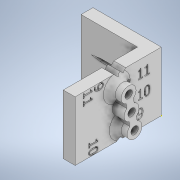
# Autodesk Inventor part: v3_gaura_9mm_semn
Saved by Autodesk Inventor 2022.6 (Build 266554000, 554)
## iProperties
Created: 2026-01-08
Part Number: v3_gaura_9mm_semn
Material: Generic
Document SubType Name: Modeling
Designer: Dragos Macovei
Density: 1 g/cm^3
Appearance: Default
Author: Dragos Macovei
Autodesk Inventor part; units mm, degrees
ref_plane "YZ Plane" through (0, 0, 0) normal (1, 0, 0) x (0, 1, 0)
ref_plane "XZ Plane" through (0, 0, 0) normal (0, 1, 0) x (-1, 0, 0)
ref_plane "XY Plane" through (0, 0, 0) normal (0, 0, 1) x (1, 0, 0)
sketch "Sketch1" plane through (0, 0, 0) normal (0, 1, 0) x (-1, 0, 0)
  line L0 (0, 0) -> (23, 0)
  line L1 (23, 4) -> (4, 4)
  line L2 (4, 4) -> (4, 29)
  line L3 (4, 29) -> (0, 29)
  line L4 (0, 29) -> (0, 0)
  line L5 (23, 4) -> (23, 0)
  point P0 (4, 16.5)
  point P1 (27, 14.5)
  point P2 (25, 29)
  dimension "d1" = 4
  dimension "d3" = 4
  dimension "d4" = 25
  dimension "d5" = 25
  constraints: 12 end point, 4 perpendicular, 1 horizontal, 1 midpoint
  measures "d1" distance from line of L4 point (4, 16.5)
  measures "d3" distance between parallel lines of L0 L1
  measures "d4" distance from line of L1 point (25, 29)
  measures "d5" distance from line of L1 L3.end
extrude "Extrusion1" add sketch "Sketch1" along normal blind 20
sketch "Sketch2" plane through (0, 0, 29) normal (1, 0, 0) x (0, 0, -1)
  point P0 (29, 0)
sketch "Sketch7" plane through (0, 0, 0) normal (0, 0, -1) x (-1, 0, 0)
  line L0 (0, 0) -> (23, 0) projected
  line L1 (0, 20) -> (23, 20) projected
  line L2 (0, 0) -> (0, 20) projected
  line L3 (13.5, 10) -> (10.5, 10)
  line L4 (10.5, 10) -> (10.5, 9.5)
  line L5 (10.5, 9.5) -> (13.5, 9.5)
  line L6 (13.5, 9.5) -> (13.5, 10)
  line L7 (13.5, 10) -> (16.5, 10)
  line L8 (16.5, 10) -> (16.5, 9.5)
  line L9 (16.5, 9.5) -> (13.5, 9.5)
  line L10 (13.5, 9.5) -> (13.5, 10)
  line L11 (16.5, 10) -> (10.5, 10)
  line L12 (10.5, 10) -> (10.5, 10.5)
  line L13 (10.5, 10.5) -> (16.5, 10.5)
  line L14 (16.5, 10.5) -> (16.5, 10)
  line L15 (23, 0) -> (23, 20) projected
  dimension "d25" = 3
  dimension "d26" = 0.5
  dimension "d27" = 3
  dimension "d28" = 0.5
  dimension "d29" = 0.5
  constraints: 24 end point, 6 parallel, 3 horizontal, 3 perpendicular, 1 point on line
  measures "d25" distance of L5.end L4.end
  measures "d26" distance of L4.end L3.end
  measures "d27" distance of L8.end L9.end
  measures "d28" distance of L7.end L8.end
  measures "d29" distance of L11.end L12.end
extrude "Extrusion6" cut sketch "Sketch7" against normal through all contours L6 L5 L4 L3 | L7 L8 L9 L6 | L3 L12 L13 L14 L7
fillet "Fillet3" radius 3 4 edges at (-13.5, 10.5, 0) (-16.5, 10, 0) (-13.5, 9.5, 0) (-10.5, 10, 0) inverted yes
sketch "Sketch8" plane through (0, 0, 0) normal (0, 0, -1) x (-1, 0, 0)
  line L0 (16.5, 9.5) -> (16.5, 10.5) projected
  line L1 (10.5, 10.5) -> (10.5, 9.5) projected
  line L2 (7.5, 13.5) -> (7.5, 6.5) projected
  line L3 (19.5, 6.5) -> (19.5, 13.5) projected
  line L4 (16.5, 10.5) -> (19.5, 10)
  line L5 (16.5, 9.5) -> (19.5, 10)
  line L6 (16.5, 10.5) -> (10.5, 10.5) projected
  line L7 (10.5, 10.5) -> (7.5, 10)
  line L8 (7.5, 10) -> (10.5, 9.5)
  point P0 (0, 0)
  point P1 (16.5, 10)
  point P2 (10.5, 10)
  constraints: 8 end point, 4 midpoint, 2 parallel
extrude "Extrusion7" cut sketch "Sketch8" along normal through all both and the other way through all
sketch "Sketch9" plane through (-4, 0, 4) normal (-1, 0, 0) x (0, 0, 1)
  circle A0 centre (9, 4.25) radius 1.25
  circle A1 centre (10, 10) radius 1.25
  circle A2 centre (11, 15.75) radius 1.25
  line L0 (0, 0) -> (25, 0) projected
  line L1 (0, 0) -> (0, 20) projected
  line L2 (0, 20) -> (25, 20) projected
  point P0 (-4, 0)
  point P1 (10, 20)
  dimension "d35" = 2.5
  dimension "d36" = 2.5
  dimension "d37" = 2.5
  dimension "d40" = 3
  dimension "d41" = 9
  dimension "d42" = 10
  dimension "d43" = 11
  dimension "d48" = 3
  dimension "d49" = 5.75
  constraints: 3 centre point
  measures "d35" diameter of A0
  measures "d36" diameter of A1
  measures "d37" diameter of A2
  measures "d40" distance edge to line of A0 L0
  measures "d41" distance from line of L1 A0.centre
  measures "d42" distance from line of L1 A1.centre
  measures "d43" distance from line of L1 A2.centre
  measures "d48" distance edge to line of A2 L2
  measures "d49" vertical distance of A1.centre A0.centre
extrude "Extrusion8" cut sketch "Sketch9" against normal through all
sketch "Sketch10" plane through (-4, 0, 4) normal (-1, 0, 0) x (0, 0, 1)
  circle A0 centre (11, 15.75) radius 1.25 projected
  circle A1 centre (10, 10) radius 1.25 projected
  circle A2 centre (9, 4.25) radius 1.25 projected
  line L0 (0, 0) -> (25, 0) projected
  line L1 (25, 0) -> (25, 20) projected
  line L2 (0, 20) -> (25, 20) projected
  line L3 (0, 0) -> (0, 20) projected
  line L4 (0, 0) -> (25, 0) projected
  line L5 (25, 20) -> (-4, 20) projected
  circle A3 centre (10, 0) radius 1
  line L6 (9, 0) -> (10, 1)
  line L7 (11, 0) -> (10, 1)
  circle A4 centre (11, 20) radius 1
  circle A5 centre (9, 20) radius 1
  line L8 (8, 20) -> (9, 19)
  line L9 (10, 20) -> (9, 19)
  line L10 (10, 20) -> (11, 19)
  line L11 (12, 20) -> (11, 19)
  point P0 (-4, 0)
  point P1 (11, 0)
  point P2 (11, 0)
  constraints: 12 end point, 9 point on circle, 8 point on line, 4 perpendicular, 3 centre point, 3 coincident
extrude "Extrusion9" cut sketch "Sketch10" against normal through all contours L6 L7 L0 | L2 L9 L8 | L2 L11 L10
sketch "Sketch11" plane through (0, 0, 29) normal (1, 0, 0) x (0, 0, -1)
  line L0 (14, 19) -> (13, 20) projected
  line L1 (0, 20) -> (13, 20) projected
  line L2 (0, 0) -> (0, 20) projected
  line L3 (0, 0) -> (14, 0) projected
  line L4 (14, 0) -> (15, 1) projected
  line L5 (15, 1) -> (16, 0) projected
  line L6 (16, 0) -> (29, 0) projected
  line L7 (29, 0) -> (29, 20) projected
  line L8 (17, 20) -> (29, 20) projected
  line L9 (17, 20) -> (16, 19) projected
  line L10 (16, 19) -> (15, 20) projected
  line L11 (15, 20) -> (14, 19) projected
  circle A0 centre (14, 15.75) radius 1.25 projected
  circle A1 centre (15, 10) radius 1.25 projected
  circle A2 centre (16, 4.25) radius 1.25 projected
  circle A3 centre (14, 15.75) radius 2.5
  circle A4 centre (15, 10) radius 2.5
  circle A5 centre (16, 4.25) radius 2.5
  dimension "d52" = 5
  dimension "d53" = 5
  dimension "d54" = 5
  constraints: 3 centre point, 3 coincident
  measures "d52" diameter of A3
  measures "d53" diameter of A4
  measures "d54" diameter of A5
extrude "Extrusion10" add sketch "Sketch11" along normal blind 4 contours A3 | A4 | A5
fillet "Fillet4" radius 2 1 edges at (0, 15.75, 17.5)
fillet "Fillet5" radius 2 1 edges at (0, 4.25, 15.5)
sketch "Sketch12" plane through (4, 10, 14) normal (1, 0, 0) x (0, 0, -1)
  circle A0 centre (-1, 5.75) radius 1.25 projected
  line L0 (-2.25, 5.75) -> (-0.2318, -5.9623)
  circle A1 centre (1, -5.75) radius 1.25 projected
  line L1 (-0.0128, 7.3687) -> (2.5592, -7.42)
  circle A2 centre (0, 0) radius 2.5 projected
  circle A3 centre (0, 0) radius 1.25 projected
  circle A4 centre (-1, 5.75) radius 2.5 projected
  circle A5 centre (-1, 5.75) radius 1.25 projected
  circle A6 centre (1, -5.75) radius 2.5 projected
  circle A7 centre (1, -5.75) radius 1.25 projected
  point P0 (14, -10)
  point P1 (-0.5995, -3.8286)
  point P2 (1.8606, -3.4028)
  point P3 (1.6025, -1.9189)
  point P4 (-0.8544, -2.3495)
  point P5 (0.6025, 3.8311)
  point P6 (-1.8445, 3.397)
  point P7 (-1.5914, 1.928)
  point P8 (0.8606, 2.3472)
  constraints: 4 end point, 1 horizontal alignment, 6 other
extrude "Extrusion11" add sketch "Sketch12" against normal blind 4 contours L1 A2 L0 A4 | A2 L1 A6 L0
sketch "Sketch13" plane through (0, 0, 29) normal (1, 0, 0) x (0, 0, -1)
  line L0 (20.7455, 17.3) -> (27.0793, 17.3) construction
  line L1 (27.0793, 17.3) -> (27.0793, 14.5773) construction
  line L2 (27.0793, 14.5773) -> (20.7455, 14.5773) construction
  line L3 (20.7455, 14.5773) -> (20.7455, 17.3) construction
  arc A0 (17.479, 0) -> (17.0831, 8.6177) centre (16, 4.25) ccw projected
  line L4 (17.479, 0) -> (29, 0) projected
  line L5 (29, 0) -> (29, 20) projected
  line L6 (17, 20) -> (29, 20) projected
  line L7 (17, 20) -> (16.495, 19.495) projected
  arc A1 (16.4941, 12.0044) -> (16.495, 19.495) centre (14, 15.75) ccw projected
  arc A2 (17.0831, 8.6177) -> (16.4941, 12.0044) centre (15, 10) ccw projected
  line L8 (20.7455, 11.3312) -> (27.0847, 11.3312) construction
  line L9 (27.0847, 11.3312) -> (27.0847, 8.61) construction
  line L10 (27.0847, 8.61) -> (20.7455, 8.61) construction
  line L11 (20.7455, 8.61) -> (20.7455, 11.3312) construction
  line L12 (20.7455, 5.8) -> (27.0538, 5.8) construction
  line L13 (27.0538, 5.8) -> (27.0538, 3.0514) construction
  line L14 (27.0538, 3.0514) -> (20.7455, 3.0514) construction
  line L15 (20.7455, 3.0514) -> (20.7455, 5.8) construction
  line L16 (20.7455, 15.75) -> (20.7455, 4.25)
  line L17 (22.6944, 14.2421) -> (21.2074, 14.2421)
  line L18 (21.2074, 14.2421) -> (21.2074, 14.5533)
  line L19 (21.2074, 14.5533) -> (21.7607, 14.5533)
  line L20 (21.7607, 14.5533) -> (21.7607, 16.596)
  line L21 (21.7607, 16.596) -> (21.2074, 16.596)
  line L22 (21.2074, 16.596) -> (21.2074, 16.8752)
  spline S0 degree 2 poles (21.2074, 16.8752) (21.5211, 16.8752) (21.8175, 17.053) (21.8373, 17.3) knots 0 0 0 1 2 2 2
  line L23 (21.8373, 17.3) -> (22.1534, 17.3)
  line L24 (22.1534, 17.3) -> (22.1534, 14.5533)
  line L25 (22.1534, 14.5533) -> (22.6944, 14.5533)
  line L26 (22.6944, 14.5533) -> (22.6944, 14.2421)
  line L27 (24.9816, 14.2421) -> (23.4947, 14.2421)
  line L28 (23.4947, 14.2421) -> (23.4947, 14.5533)
  line L29 (23.4947, 14.5533) -> (24.0479, 14.5533)
  line L30 (24.0479, 14.5533) -> (24.0479, 16.596)
  line L31 (24.0479, 16.596) -> (23.4947, 16.596)
  line L32 (23.4947, 16.596) -> (23.4947, 16.8752)
  spline S1 degree 2 poles (23.4947, 16.8752) (23.8084, 16.8752) (24.1048, 17.053) (24.1245, 17.3) knots 0 0 0 1 2 2 2
  line L33 (24.1245, 17.3) -> (24.4407, 17.3)
  line L34 (24.4407, 17.3) -> (24.4407, 14.5533)
  line L35 (24.4407, 14.5533) -> (24.9816, 14.5533)
  line L36 (24.9816, 14.5533) -> (24.9816, 14.2421)
  line L37 (22.6944, 8.2215) -> (21.2074, 8.2215)
  line L38 (21.2074, 8.2215) -> (21.2074, 8.5327)
  line L39 (21.2074, 8.5327) -> (21.7607, 8.5327)
  line L40 (21.7607, 8.5327) -> (21.7607, 10.5754)
  line L41 (21.7607, 10.5754) -> (21.2074, 10.5754)
  line L42 (21.2074, 10.5754) -> (21.2074, 10.8545)
  spline S2 degree 2 poles (21.2074, 10.8545) (21.5211, 10.8545) (21.8175, 11.0324) (21.8373, 11.2794) knots 0 0 0 1 2 2 2
  line L43 (21.8373, 11.2794) -> (22.1534, 11.2794)
  line L44 (22.1534, 11.2794) -> (22.1534, 8.5327)
  line L45 (22.1534, 8.5327) -> (22.6944, 8.5327)
  line L46 (22.6944, 8.5327) -> (22.6944, 8.2215)
  spline S3 degree 2 poles (25.152, 9.7455) (25.152, 8.9254) (24.6753, 8.1573) (24.1789, 8.1573) knots 0 0 0 1 2 2 2
  spline S4 degree 2 poles (24.1789, 8.1573) (23.675, 8.1573) (23.2032, 8.9403) (23.2032, 9.743) knots 0 0 0 1 2 2 2
  spline S5 degree 2 poles (23.2032, 9.743) (23.2032, 10.568) (23.6799, 11.3312) (24.1789, 11.3312) knots 0 0 0 1 2 2 2
  spline S6 degree 2 poles (24.1789, 11.3312) (24.6803, 11.3312) (25.152, 10.5408) (25.152, 9.7455) knots 0 0 0 1 2 2 2
  spline S7 degree 2 poles (24.6284, 8.8168) (24.6877, 8.9674) (24.7371, 9.4318) (24.7371, 9.7455) knots 0 0 0 1 2 2 2
  spline S8 degree 2 poles (24.7371, 9.7455) (24.7371, 10.0592) (24.6877, 10.5211) (24.6259, 10.6767) knots 0 0 0 1 2 2 2
  spline S9 degree 2 poles (24.6259, 10.6767) (24.5642, 10.8323) (24.3493, 10.9928) (24.1789, 10.9928) knots 0 0 0 1 2 2 2
  spline S10 degree 2 poles (24.1789, 10.9928) (24.0084, 10.9928) (23.7886, 10.8323) (23.7244, 10.6717) knots 0 0 0 1 2 2 2
  spline S11 degree 2 poles (23.7244, 10.6717) (23.6626, 10.5161) (23.6182, 10.0419) (23.6182, 9.743) knots 0 0 0 1 2 2 2
  spline S12 degree 2 poles (23.6182, 9.743) (23.6182, 9.4219) (23.6577, 8.9921) (23.7219, 8.8242) knots 0 0 0 1 2 2 2
  spline S13 degree 2 poles (23.7219, 8.8242) (23.7812, 8.6661) (24.001, 8.4957) (24.1789, 8.4957) knots 0 0 0 1 2 2 2
  spline S14 degree 2 poles (24.1789, 8.4957) (24.3468, 8.4957) (24.5666, 8.6562) (24.6284, 8.8168) knots 0 0 0 1 2 2 2
  spline S15 degree 2 poles (20.8839, 4.7478) (20.8839, 4.9824) (21.037, 5.3727) (21.1704, 5.5135) knots 0 0 0 1 2 2 2
  spline S16 degree 2 poles (21.1704, 5.5135) (21.2963, 5.6493) (21.6644, 5.8) (21.8521, 5.8) knots 0 0 0 1 2 2 2
  spline S17 degree 2 poles (21.8521, 5.8) (22.0621, 5.8) (22.4029, 5.6592) (22.5289, 5.5258) knots 0 0 0 1 2 2 2
  spline S18 degree 2 poles (22.5289, 5.5258) (22.687, 5.3579) (22.8599, 4.8145) (22.8599, 4.397) knots 0 0 0 1 2 2 2
  spline S19 degree 2 poles (22.8599, 4.397) (22.8599, 4.0191) (22.6894, 3.3423) (22.5239, 3.1176) knots 0 0 0 1 2 2 2
  spline S20 degree 2 poles (22.5239, 3.1176) (22.3486, 2.8804) (21.8546, 2.631) (21.4939, 2.631) knots 0 0 0 1 2 2 2
  spline S21 degree 2 poles (21.4939, 2.631) (21.4124, 2.631) (21.2272, 2.6483) (21.1481, 2.673) knots 0 0 0 1 2 2 2
  line L47 (21.1481, 2.673) -> (21.1481, 3.0657)
  line L48 (21.1481, 3.0657) -> (21.1679, 3.0657)
  spline S22 degree 2 poles (21.1679, 3.0657) (21.2198, 3.0361) (21.4371, 2.9842) (21.5483, 2.9842) knots 0 0 0 1 2 2 2
  spline S23 degree 2 poles (21.5483, 2.9842) (21.9484, 2.9842) (22.4054, 3.5128) (22.4375, 4.0018) knots 0 0 0 1 2 2 2
  spline S24 degree 2 poles (22.4375, 4.0018) (22.2745, 3.8907) (21.9781, 3.7894) (21.8027, 3.7894) knots 0 0 0 1 2 2 2
  spline S25 degree 2 poles (21.8027, 3.7894) (21.6347, 3.7894) (21.3556, 3.8635) (21.2148, 3.9697) knots 0 0 0 1 2 2 2
  spline S26 degree 2 poles (21.2148, 3.9697) (21.0518, 4.0957) (20.8839, 4.4785) (20.8839, 4.7478) knots 0 0 0 1 2 2 2
  spline S27 degree 2 poles (22.4474, 4.4884) (22.4474, 4.7972) (22.3338, 5.1874) (22.2325, 5.2936) knots 0 0 0 1 2 2 2
  spline S28 degree 2 poles (22.2325, 5.2936) (22.1436, 5.3924) (21.9583, 5.4665) (21.8496, 5.4665) knots 0 0 0 1 2 2 2
  spline S29 degree 2 poles (21.8496, 5.4665) (21.5977, 5.4665) (21.2988, 5.1059) (21.2988, 4.7651) knots 0 0 0 1 2 2 2
  spline S30 degree 2 poles (21.2988, 4.7651) (21.2988, 4.5724) (21.3976, 4.3229) (21.5063, 4.234) knots 0 0 0 1 2 2 2
  spline S31 degree 2 poles (21.5063, 4.234) (21.5853, 4.1698) (21.7805, 4.1278) (21.8941, 4.1278) knots 0 0 0 1 2 2 2
  spline S32 degree 2 poles (21.8941, 4.1278) (22.025, 4.1278) (22.3263, 4.2192) (22.44, 4.2958) knots 0 0 0 1 2 2 2
  spline S33 degree 2 poles (22.44, 4.2958) (22.4424, 4.3254) (22.4474, 4.4267) (22.4474, 4.4884) knots 0 0 0 1 2 2 2
  point P0 (20.7455, 9.7812)
  dimension "d61" = 1.55
  dimension "d62" = 1.55
  dimension "d63" = 1.55
  dimension "d64" = 0
  constraints: 5 coincident, 3 point on line, 2 end point, 1 vertical, 6 other
  measures "d61" distance of point (20.746, 4.25) point (20.746, 5.8)
  measures "d62" distance of point (20.746, 9.781) point (20.746, 11.331)
  measures "d63" distance of L16.start point (20.746, 17.3)
  measures "d64" vertical distance of L16.start A1.centre
extrude "Extrusion12" cut sketch "Sketch13" against normal blind 1.5 contours L17 L18 L19 L20 L21 L22 S0 L23 L24 L25 L26 | L27 L28 L29 L30 L31 L32 S1 L33 L34 L35 L36 | L37 L38 L39 L40 L41 L42 S2 L43 L44 L45 L46 | S3 S4 S5 S6 | S15 S16 S17 S18 S19 S20 S21 L47 L48 S22 S23 S24 S25 S26
sketch "Sketch14" plane through (0, 0, 29) normal (1, 0, 0) x (0, 0, -1)
  line L0 (7.6929, 4.5921) -> (7.6929, 0.0177) construction
  line L1 (7.6929, 0.0177) -> (4.519, 0.0177) construction
  line L2 (4.519, 0.0177) -> (4.519, 4.5921) construction
  line L3 (4.519, 4.5921) -> (7.6929, 4.5921) construction
  line L4 (9.5182, 19.9679) -> (9.5182, 15.3934) construction
  line L5 (9.5182, 15.3934) -> (6.3442, 15.3934) construction
  line L6 (6.3442, 15.3934) -> (6.3442, 19.9679) construction
  line L7 (6.3442, 19.9679) -> (9.5182, 19.9679) construction
  line L8 (2.5663, 20.0123) -> (5.7403, 20.0123) construction
  line L9 (5.7403, 20.0123) -> (5.7403, 15.4378) construction
  line L10 (5.7403, 15.4378) -> (2.5663, 15.4378) construction
  line L11 (2.5663, 15.4378) -> (2.5663, 20.0123) construction
  spline S0 degree 2 poles (8.466, 19.8295) (8.7006, 19.8295) (9.0909, 19.6764) (9.2317, 19.543) knots 0 0 0 1 2 2 2
  spline S1 degree 2 poles (9.2317, 19.543) (9.3675, 19.417) (9.5182, 19.049) (9.5182, 18.8613) knots 0 0 0 1 2 2 2
  spline S2 degree 2 poles (9.5182, 18.8613) (9.5182, 18.6513) (9.3774, 18.3105) (9.244, 18.1845) knots 0 0 0 1 2 2 2
  spline S3 degree 2 poles (9.244, 18.1845) (9.0761, 18.0264) (8.5327, 17.8535) (8.1152, 17.8535) knots 0 0 0 1 2 2 2
  spline S4 degree 2 poles (8.1152, 17.8535) (7.7373, 17.8535) (7.0605, 18.024) (6.8358, 18.1894) knots 0 0 0 1 2 2 2
  spline S5 degree 2 poles (6.8358, 18.1894) (6.5986, 18.3648) (6.3492, 18.8588) (6.3492, 19.2194) knots 0 0 0 1 2 2 2
  spline S6 degree 2 poles (6.3492, 19.2194) (6.3492, 19.301) (6.3665, 19.4862) (6.3912, 19.5652) knots 0 0 0 1 2 2 2
  line L12 (6.3912, 19.5652) -> (6.7839, 19.5652)
  line L13 (6.7839, 19.5652) -> (6.7839, 19.5455)
  spline S7 degree 2 poles (6.7839, 19.5455) (6.7543, 19.4936) (6.7024, 19.2763) (6.7024, 19.1651) knots 0 0 0 1 2 2 2
  spline S8 degree 2 poles (6.7024, 19.1651) (6.7024, 18.765) (7.231, 18.308) (7.72, 18.2759) knots 0 0 0 1 2 2 2
  spline S9 degree 2 poles (7.72, 18.2759) (7.6089, 18.4389) (7.5076, 18.7353) (7.5076, 18.9107) knots 0 0 0 1 2 2 2
  spline S10 degree 2 poles (7.5076, 18.9107) (7.5076, 19.0787) (7.5817, 19.3578) (7.6879, 19.4986) knots 0 0 0 1 2 2 2
  spline S11 degree 2 poles (7.6879, 19.4986) (7.8139, 19.6616) (8.1967, 19.8295) (8.466, 19.8295) knots 0 0 0 1 2 2 2
  spline S12 degree 2 poles (8.2066, 18.266) (8.5154, 18.266) (8.9056, 18.3796) (9.0119, 18.4809) knots 0 0 0 1 2 2 2
  spline S13 degree 2 poles (9.0119, 18.4809) (9.1107, 18.5698) (9.1848, 18.7551) (9.1848, 18.8638) knots 0 0 0 1 2 2 2
  spline S14 degree 2 poles (9.1848, 18.8638) (9.1848, 19.1157) (8.8241, 19.4146) (8.4833, 19.4146) knots 0 0 0 1 2 2 2
  spline S15 degree 2 poles (8.4833, 19.4146) (8.2906, 19.4146) (8.0411, 19.3158) (7.9522, 19.2071) knots 0 0 0 1 2 2 2
  spline S16 degree 2 poles (7.9522, 19.2071) (7.888, 19.1281) (7.846, 18.9329) (7.846, 18.8193) knots 0 0 0 1 2 2 2
  spline S17 degree 2 poles (7.846, 18.8193) (7.846, 18.6884) (7.9374, 18.387) (8.014, 18.2734) knots 0 0 0 1 2 2 2
  spline S18 degree 2 poles (8.014, 18.2734) (8.0436, 18.271) (8.1449, 18.266) (8.2066, 18.266) knots 0 0 0 1 2 2 2
  line L14 (2.6824, 18.0634) -> (2.6824, 19.5504)
  line L15 (2.6824, 19.5504) -> (2.9936, 19.5504)
  line L16 (2.9936, 19.5504) -> (2.9936, 18.9971)
  line L17 (2.9936, 18.9971) -> (5.0363, 18.9971)
  line L18 (5.0363, 18.9971) -> (5.0363, 19.5504)
  line L19 (5.0363, 19.5504) -> (5.3155, 19.5504)
  spline S19 degree 2 poles (5.3155, 19.5504) (5.3155, 19.2367) (5.4933, 18.9403) (5.7403, 18.9205) knots 0 0 0 1 2 2 2
  line L20 (5.7403, 18.9205) -> (5.7403, 18.6044)
  line L21 (5.7403, 18.6044) -> (2.9936, 18.6044)
  line L22 (2.9936, 18.6044) -> (2.9936, 18.0634)
  line L23 (2.9936, 18.0634) -> (2.6824, 18.0634)
  line L24 (2.6824, 15.7762) -> (2.6824, 17.2631)
  line L25 (2.6824, 17.2631) -> (2.9936, 17.2631)
  line L26 (2.9936, 17.2631) -> (2.9936, 16.7099)
  line L27 (2.9936, 16.7099) -> (5.0363, 16.7099)
  line L28 (5.0363, 16.7099) -> (5.0363, 17.2631)
  line L29 (5.0363, 17.2631) -> (5.3155, 17.2631)
  spline S20 degree 2 poles (5.3155, 17.2631) (5.3155, 16.9495) (5.4933, 16.6531) (5.7403, 16.6333) knots 0 0 0 1 2 2 2
  line L30 (5.7403, 16.6333) -> (5.7403, 16.3171)
  line L31 (5.7403, 16.3171) -> (2.9936, 16.3171)
  line L32 (2.9936, 16.3171) -> (2.9936, 15.7762)
  line L33 (2.9936, 15.7762) -> (2.6824, 15.7762)
  line L34 (4.5832, 2.6433) -> (4.5832, 4.1302)
  line L35 (4.5832, 4.1302) -> (4.8944, 4.1302)
  line L36 (4.8944, 4.1302) -> (4.8944, 3.577)
  line L37 (4.8944, 3.577) -> (6.9371, 3.577)
  line L38 (6.9371, 3.577) -> (6.9371, 4.1302)
  line L39 (6.9371, 4.1302) -> (7.2162, 4.1302)
  spline S21 degree 2 poles (7.2162, 4.1302) (7.2162, 3.8165) (7.3941, 3.5201) (7.6411, 3.5004) knots 0 0 0 1 2 2 2
  line L40 (7.6411, 3.5004) -> (7.6411, 3.1842)
  line L41 (7.6411, 3.1842) -> (4.8944, 3.1842)
  line L42 (4.8944, 3.1842) -> (4.8944, 2.6433)
  line L43 (4.8944, 2.6433) -> (4.5832, 2.6433)
  spline S22 degree 2 poles (6.1072, 0.1856) (5.2871, 0.1856) (4.519, 0.6623) (4.519, 1.1588) knots 0 0 0 1 2 2 2
  spline S23 degree 2 poles (4.519, 1.1588) (4.519, 1.6627) (5.302, 2.1345) (6.1047, 2.1345) knots 0 0 0 1 2 2 2
  spline S24 degree 2 poles (6.1047, 2.1345) (6.9297, 2.1345) (7.6929, 1.6578) (7.6929, 1.1588) knots 0 0 0 1 2 2 2
  spline S25 degree 2 poles (7.6929, 1.1588) (7.6929, 0.6574) (6.9025, 0.1856) (6.1072, 0.1856) knots 0 0 0 1 2 2 2
  spline S26 degree 2 poles (5.1785, 0.7093) (5.3291, 0.65) (5.7935, 0.6006) (6.1072, 0.6006) knots 0 0 0 1 2 2 2
  spline S27 degree 2 poles (6.1072, 0.6006) (6.4209, 0.6006) (6.8828, 0.65) (7.0384, 0.7117) knots 0 0 0 1 2 2 2
  spline S28 degree 2 poles (7.0384, 0.7117) (7.194, 0.7735) (7.3545, 0.9884) (7.3545, 1.1588) knots 0 0 0 1 2 2 2
  spline S29 degree 2 poles (7.3545, 1.1588) (7.3545, 1.3292) (7.194, 1.5491) (7.0334, 1.6133) knots 0 0 0 1 2 2 2
  spline S30 degree 2 poles (7.0334, 1.6133) (6.8778, 1.675) (6.4036, 1.7195) (6.1047, 1.7195) knots 0 0 0 1 2 2 2
  spline S31 degree 2 poles (6.1047, 1.7195) (5.7836, 1.7195) (5.3538, 1.68) (5.1859, 1.6158) knots 0 0 0 1 2 2 2
  spline S32 degree 2 poles (5.1859, 1.6158) (5.0278, 1.5565) (4.8574, 1.3366) (4.8574, 1.1588) knots 0 0 0 1 2 2 2
  spline S33 degree 2 poles (4.8574, 1.1588) (4.8574, 0.9908) (5.0179, 0.771) (5.1785, 0.7093) knots 0 0 0 1 2 2 2
  point P0 (29, 0)
  constraints: 6 other
extrude "Extrusion13" cut sketch "Sketch14" against normal blind 1.5
sketch "Sketch15" plane through (-4, 0, 4) normal (-1, 0, 0) x (0, 0, 1)
  circle A0 centre (9, 4.25) radius 1.25 projected
  circle A1 centre (10, 10) radius 1.25 projected
  circle A2 centre (11, 15.75) radius 1.25 projected
  line L0 (12, 20) -> (11, 19) projected
  line L1 (11, 19) -> (10, 20) projected
  line L2 (10, 20) -> (9, 19) projected
  line L3 (9, 19) -> (8, 20) projected
  line L4 (0, 20) -> (8, 20) projected
  line L5 (0, 0) -> (0, 20) projected
  line L6 (0, 0) -> (9, 0) projected
  line L7 (9, 0) -> (10, 1) projected
  line L8 (10, 1) -> (11, 0) projected
  line L9 (11, 0) -> (25, 0) projected
  line L10 (25, 0) -> (25, 20) projected
  line L11 (12, 20) -> (25, 20) projected
  line L12 (9, 4.25) -> (4.75, 4.25)
  line L13 (10, 10) -> (5.6041, 10)
  line L14 (11, 15.75) -> (5.75, 15.75)
  arc A3 (9.1394, 12.3472) -> (8.3975, 8.0811) centre (10, 10) ccw projected
  arc A4 (8.1394, 6.5972) -> (10.5995, 6.1714) centre (9, 4.25) ccw projected
  arc A5 (11.8445, 13.397) -> (9.3975, 13.8311) centre (11, 15.75) ccw projected
  line L15 (4.5, 3.75) -> (6.5, 3.75)
  line L16 (6.5, 3.75) -> (6.5, 4.75)
  line L17 (6.5, 4.75) -> (4.5, 4.75)
  line L18 (4.5, 4.75) -> (4.5, 3.75)
  line L19 (5.5, 9.5) -> (7.5, 9.5)
  line L20 (7.5, 9.5) -> (7.5, 10.5)
  line L21 (7.5, 10.5) -> (5.5, 10.5)
  line L22 (5.5, 10.5) -> (5.5, 9.5)
  line L23 (6.5, 15.25) -> (8.5, 15.25)
  line L24 (8.5, 15.25) -> (8.5, 16.25)
  line L25 (8.5, 16.25) -> (6.5, 16.25)
  line L26 (6.5, 15.25) -> (6.5, 16.25)
  line L27 (4.5, 4.25) -> (5, 3.75)
  line L28 (4.5, 4.25) -> (5, 4.75)
  arc A6 (8.1394, 6.5972) -> (10.5995, 6.1714) centre (9, 4.25) ccw projected
  line L29 (6.5, 4.25) -> (6, 3.75)
  line L30 (6, 4.75) -> (6.5, 4.25)
  line L31 (5.5, 10) -> (6, 9.5)
  line L32 (5.5, 10) -> (6, 10.5)
  line L33 (7.5, 10) -> (7, 9.5)
  line L34 (7, 10.5) -> (7.5, 10)
  line L35 (6.5, 15.75) -> (7, 15.25)
  line L36 (6.5, 15.75) -> (7, 16.25)
  line L37 (8.5, 15.75) -> (8, 16.25)
  line L38 (8.5, 15.75) -> (8, 15.25)
  point P0 (-4, 0)
  point P1 (7, 16.25)
  dimension "d69" = 4.25
  dimension "d70" = 0.5
  dimension "d71" = 0.5
  dimension "d72" = 0.5
  dimension "d73" = 0.5
  dimension "d74" = 0.5
  dimension "d75" = 0.5
  dimension "d76" = 2
  dimension "d77" = 2
  dimension "d79" = 2
  constraints: 54 end point, 11 point on line, 10 perpendicular, 9 parallel, 6 horizontal, 6 midpoint, 3 tangent, 1 point on circle
  measures "d69" distance of L12.start L12.end
  measures "d70" distance between parallel lines of L12 L15
  measures "d71" distance between parallel lines of L12 L17
  measures "d72" distance between parallel lines of L13 L21
  measures "d73" distance between parallel lines of L13 L19
  measures "d74" distance between parallel lines of L14 L23
  measures "d75" distance between parallel lines of L25 L14
  measures "d76" distance between parallel lines of L16 L18
  measures "d77" distance between parallel lines of L20 L22
  measures "d79" distance between parallel lines of L24 L26
extrude "Extrusion14" cut sketch "Sketch15" against normal through all contours L38 L23 L35 L14 | L14 L36 L25 L37 | L27 L28 L17 L30 L29 L15 | L31 L32 L21 L34 L33 L19
equation "\"d26\" = d28"
equation "\"d29\" = d26"
body "Solid1"
